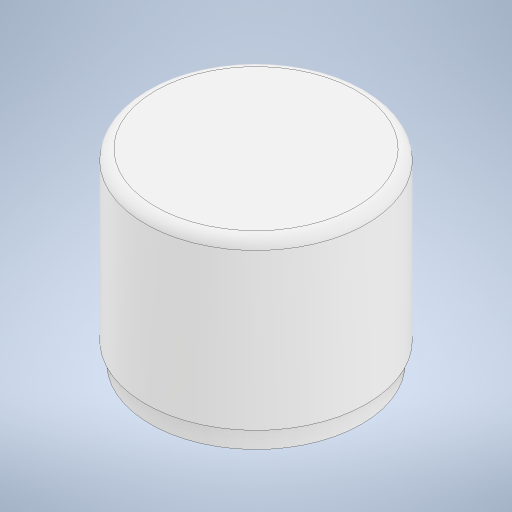
# Autodesk Inventor part: рассеиватель короткий
Saved by Autodesk Inventor 2024 (Build 280153000, 153)
## iProperties
Created: 2026-05-18
Part Number: рассеиватель короткий
Material: Типовые
Document SubType Name: Modeling
Designer: Pavel
Density: 1 g/cm^3
Appearance: По умолчанию
Author: Pavel
Autodesk Inventor part; units mm, degrees
ref_plane "YZ Plane" through (0, 0, 0) normal (1, 0, 0) x (0, 1, 0)
ref_plane "XZ Plane" through (0, 0, 0) normal (0, 1, 0) x (-1, 0, 0)
ref_plane "XY Plane" through (0, 0, 0) normal (0, 0, 1) x (1, 0, 0)
sketch "Эскиз1" plane through (0, 0, 0) normal (0, 1, 0) x (-1, 0, 0)
  circle A0 centre (0, 0) radius 22
  dimension "d0" = 44
  constraints: 1 centre point, 1 coincident
  measures "d0" diameter of A0
extrude "Выдавливание1" add sketch "Эскиз1" along normal blind 37
fillet "Сопряжение1" radius 2 1 edges at (22, 37, 0)
sketch "Эскиз2" plane through (0, 0, 0) normal (0, -1, 0) x (1, 0, 0)
  circle A0 centre (0, 0) radius 20.1
  dimension "d4" = 40.2
  constraints: 1 centre point, 1 coincident
  measures "d4" diameter of A0
extrude "Выдавливание2" cut sketch "Эскиз2" against normal blind 35
sketch "Эскиз3" plane through (0, 0, 0) normal (0, -1, 0) x (1, 0, 0)
  circle A0 centre (0, 0) radius 21
  circle A1 centre (0, 0) radius 22
  dimension "d7" = 42
  dimension "d8" = 44
  constraints: 2 centre point, 2 coincident
  measures "d7" diameter of A0
  measures "d8" diameter of A1
extrude "Выдавливание3" cut sketch "Эскиз3" against normal blind 4
sketch "Эскиз4" plane through (0, 0, 0) normal (0, -1, 0) x (1, 0, 0)
  circle A0 centre (0, 0) radius 20.1 projected
  line L0 (0, 20.1) -> (0, 19.9)
  line L1 (0, 19.9) -> (0.5, 19.9)
  line L2 (0, 19.9) -> (-0.5, 19.9)
  line L3 (0.5, 19.9) -> (0.5, 20.0938)
  line L4 (-0.5, 19.9) -> (-0.5, 20.0938)
  arc A1 (0.5, 20.0938) -> (-0.5, 20.0938) centre (0, 0) ccw
  circle A2 centre (0, 0) radius 20.1
  line L5 (0, -19.9) -> (0.5, -19.9)
  line L6 (0, -19.9) -> (-0.5, -19.9)
  line L7 (0.5, -19.9) -> (0.5, -20.0938)
  line L8 (-0.5, -19.9) -> (-0.5, -20.0938)
  dimension "d11" = 0.2
  dimension "d12" = 0.5
  dimension "d13" = 0.5
  constraints: 18 end point, 7 point on circle, 3 vertical, 2 centre point, 1 coincident, 1 horizontal, 1 perpendicular
  measures "d11" distance of L0.start L0.end
  measures "d12" distance of L0.end L1.end
  measures "d13" distance of L0.end L2.end
extrude "Выдавливание4" add sketch "Эскиз4" against normal blind 1 contours L3 L1 L0 A0 | A0 L8 L6 L5 L7 | L0 L2 L4 A0
chamfer "Фаска1" distance 0.19 angle 45 1 edges at (0, 1, 19.9)
chamfer "Фаска2" distance 0.19 angle 45 1 edges at (0, 1, -19.9)
